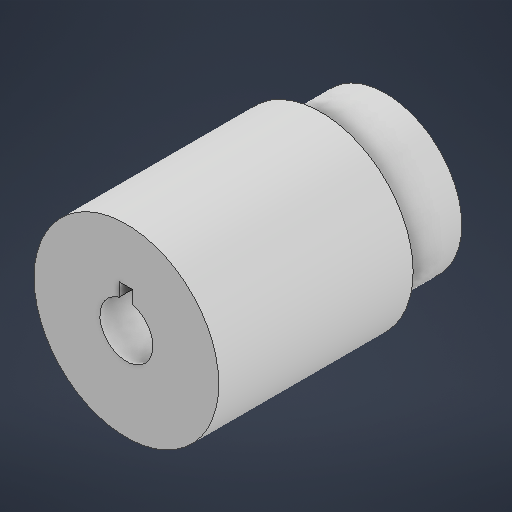
# Autodesk Inventor part: Pulley Insert
Saved by Autodesk Inventor 2026.3 (Build 303398000, 398)
## iProperties
Created: 2026-08-20
Part Number: Pulley Insert
Material: Generic
Document SubType Name: Modeling
Designer: User
Density: 1 g/cm^3
Appearance: Default
Author: User
Autodesk Inventor part; units mm, degrees
ref_plane "YZ Plane" through (0, 0, 0) normal (1, 0, 0) x (0, 1, 0)
ref_plane "XZ Plane" through (0, 0, 0) normal (0, 1, 0) x (-1, 0, 0)
ref_plane "XY Plane" through (0, 0, 0) normal (0, 0, 1) x (1, 0, 0)
sketch "Sketch1" plane through (0, 0, 0) normal (0, 0, 1) x (1, 0, 0)
  circle A0 centre (0, 0) radius 14.25
  dimension "d0" = 28.5
  constraints: 1 centre point, 1 coincident
  measures "d0" diameter of A0
extrude "Extrusion1" add sketch "Sketch1" against normal blind 30
sketch "Sketch2" plane through (0, 0, -30) normal (0, 0, -1) x (-1, 0, 0)
  circle A0 centre (0, 0) radius 11.75
  dimension "d3" = 23.5
  constraints: 1 centre point, 1 coincident
  measures "d3" diameter of A0
extrude "Extrusion2" add sketch "Sketch2" along normal blind 10
sketch "Sketch3" plane through (0, 0, 0) normal (0, 0, 1) x (1, 0, 0)
  circle A0 centre (0, 0) radius 4.1
  dimension "d6" = 8.2
  constraints: 1 centre point, 1 coincident
  measures "d6" diameter of A0
sketch "Sketch4" plane through (0, 0, 0) normal (0, 0, 1) x (1, 0, 0)
  line L0 (1, 3.9633) -> (1, 6)
  line L1 (1, 6) -> (-1.1, 6)
  line L2 (-1.1, 6) -> (-1.1, 3.9633)
  line L3 (-1.1, 2.2) -> (1, 6) construction
  line L4 (1, 2.2) -> (-1.1, 6) construction
  line L5 (-1.1, 3.9633) -> (-1.1, 2.2)
  line L6 (-1.1, 2.2) -> (1, 2.2)
  line L7 (1, 3.9633) -> (1, 2.2)
  dimension "d18" = 2.1
  dimension "d19" = 3.8
  constraints: 16 end point, 2 perpendicular, 1 parallel, 1 point on line
  measures "d18" distance of L1.end L0.end
  measures "d19" distance of L0.end L4.start
extrude "Extrusion3" cut sketch "Sketch3" against normal blind 33
extrude "Extrusion4" cut sketch "Sketch4" against normal blind 24
body "Solid1"
